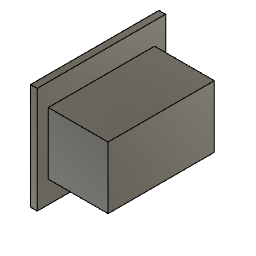
Power v1 (Autodesk Fusion 360 design; units mm, degrees)
Autodesk Fusion 360 part; units mm, degrees
sketch "Sketch1" plane through (0, 0, 0) normal (1, 0, 0) x (0, 1, 0)
  line L0 (0, 0) -> (48, 0)
  line L1 (48, 0) -> (48, 28)
  line L2 (48, 28) -> (0, 28)
  line L3 (0, 28) -> (0, 0)
  dimension "d1" = 48
  dimension "d2" = 28
  constraint horizontal L0
  constraint vertical L1
  constraint horizontal L2
  constraint vertical L3
  constraint coincident L0.start L3.end
  measures "d1" distance of L0.start L0.end
  measures "d2" distance of L0.start L2.end
extrude "Extrude1" add sketch "Sketch1" along normal blind 27
sketch "Sketch2" plane through (0, 0, 0) normal (-1, 0, 0) x (0, -1, 0)
  line L0 (0, 0) -> (0, 28)
  line L1 (0, 28) -> (-48, 28)
  line L2 (-48, 28) -> (-48, 0)
  line L3 (-48, 0) -> (0, 0)
  line L4 (-48, 28) -> (0, 0) construction
  line L5 (0, 28) -> (-48, 0) construction
  line L6 (5, -10) -> (-53, -10)
  line L7 (-53, -10) -> (-53, 38)
  line L8 (-53, 38) -> (5, 38)
  line L9 (5, 38) -> (5, -10)
  line L10 (5, -10) -> (-53, 38) construction
  line L11 (-53, -10) -> (5, 38) construction
  point P0 (-24, 14)
  dimension "d5" = 58
  dimension "d6" = 48
  constraint coincident L1.end L2.start
  constraint coincident L0.start L3.end
  constraint coincident L0.end L1.start
  constraint coincident L2.end L3.start
  constraint horizontal L6
  constraint perpendicular L6 L7
  constraint parallel L6 L8
  constraint parallel L7 L9
  constraint coincident L10 P0
  constraint coincident L11 P0
  constraint midpoint L5 P0
  measures "d5" distance of L7.end L8.end
  measures "d6" distance of L6.end L7.end
extrude "Extrude2" add sketch "Sketch2" along normal blind 3 contours L0 L1 L2 L3 | L6 L7 L8 L9
